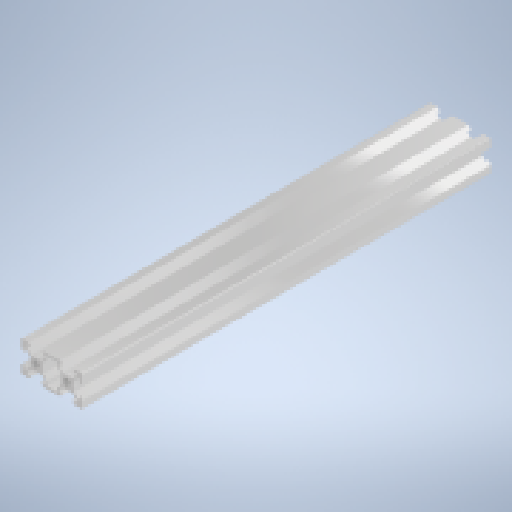
# Autodesk Inventor part: Perfil de alumínio
Saved by Autodesk Inventor 2025.2 (Build 292293000, 293)
## iProperties
Created: 2025-03-01
Part Number: Perfil de alumínio
Material: Alumínio 6061
Document SubType Name: Modeling
Designer: Cliente
Density: 2.7 g/cm^3
Appearance: Alumínio - Escuro
Mass: 397.875 g
Surface Area: 1569.42 cm^2
Volume: 147.361 cm^3
Author: Cliente
Autodesk Inventor part; units mm, degrees
ref_plane "YZ Plane" through (0, 0, 0) normal (1, 0, 0) x (0, 1, 0)
ref_plane "XZ Plane" through (0, 0, 0) normal (0, 1, 0) x (-1, 0, 0)
ref_plane "XY Plane" through (0, 0, 0) normal (0, 0, 1) x (1, 0, 0)
sketch "Esboço1" plane through (0, 0, 0) normal (0, 0, 1) x (1, 0, 0)
  line L0 (20, -10) -> (-19, -10)
  line L1 (-20, -9) -> (-20, 9)
  line L2 (-19, 10) -> (20, 10)
  line L3 (20, 10) -> (20, -10)
  line L4 (20, -10) -> (-20, 10) construction
  line L5 (-20, -10) -> (20, 10) construction
  arc A0 (-19, 10) -> (-20, 9) centre (-19, 9) ccw
  arc A1 (-20, -9) -> (-19, -10) centre (-19, -9) ccw
  circle A2 centre (-10, 0) radius 2.3
  line L6 (-6, -4) -> (-14, -4)
  line L7 (-14, -4) -> (-14, 4)
  line L8 (-14, 4) -> (-6, 4)
  line L9 (-6, 4) -> (-6, -4)
  line L10 (-6, -4) -> (-14, 4) construction
  line L11 (-14, -4) -> (-6, 4) construction
  line L12 (-13, -10) -> (-7, -10)
  line L13 (-13, -10) -> (-13, -8.2)
  line L14 (-7, -10) -> (-7, -8.2)
  line L15 (-13, -8.2) -> (-14.8, -10)
  line L16 (-13, -8.2) -> (-10.4544, -8.2) construction
  line L17 (-7, -8.2) -> (-5.2, -10)
  line L18 (-7, -8.2) -> (-4.4544, -8.2) construction
  line L19 (-15.5, -8.2) -> (-4.5, -8.2)
  line L20 (-6, -4) -> (0, -10)
  line L21 (-6.9192, -4) -> (-0.4596, -10.4596)
  line L22 (-6, -3.0808) -> (0.4596, -9.5404)
  line L23 (-4.5, -8.2) -> (-4.5, -6.4192)
  arc A3 (-9.5, -4) -> (-10.5, -4) centre (-10, -4) ccw
  arc A4 (-14, -0.5) -> (-14, 0.5) centre (-14, 0) ccw
  line L24 (-18.2, 3) -> (-20, 4.8)
  line L25 (-18.2, 5.5) -> (-18.2, -5.5)
  line L26 (-18.2, -3) -> (-20, -4.8)
  arc A5 (-10.5, 4) -> (-9.5, 4) centre (-10, 4) ccw
  line L27 (-7, 8.2) -> (-5.2, 10)
  line L28 (-4.5, 8.2) -> (-15.5, 8.2)
  line L29 (-13, 8.2) -> (-14.8, 10)
  line L30 (-6.9192, 4) -> (-0.4596, 10.4596)
  line L31 (-6, 3.0808) -> (0.4596, 9.5404)
  line L32 (-14, 3.0808) -> (-20.4596, 9.5404)
  line L33 (-13.0808, 4) -> (-19.5404, 10.4596)
  line L34 (-13.0808, -4) -> (-19.5404, -10.4596)
  line L35 (-14, -3.0808) -> (-20.4596, -9.5404)
  line L36 (-15.5, -8.2) -> (-15.5, -6.4192)
  line L37 (-18.2, -5.5) -> (-16.4192, -5.5)
  line L38 (-18.2, 5.5) -> (-16.4192, 5.5)
  line L39 (-15.5, 8.2) -> (-15.5, 6.4192)
  line L40 (-4.5, 8.2) -> (-4.5, 6.4192)
  line L41 (0, 0) -> (0, 4)
  arc A6 (20, 9) -> (19, 10) centre (19, 9) ccw
  arc A7 (19, -10) -> (20, -9) centre (19, -9) ccw
  circle A8 centre (10, 0) radius 2.3
  line L42 (6, -4) -> (14, -4)
  line L43 (14, -4) -> (14, 4)
  line L44 (14, 4) -> (6, 4)
  line L45 (6, 4) -> (6, -4)
  line L46 (13, -8.2) -> (14.8, -10)
  line L47 (7, -8.2) -> (5.2, -10)
  line L48 (15.5, -8.2) -> (4.5, -8.2)
  line L49 (6.9192, -4) -> (0.4596, -10.4596)
  line L50 (6, -3.0808) -> (-0.4596, -9.5404)
  line L51 (4.5, -8.2) -> (4.5, -6.4192)
  arc A9 (10.5, -4) -> (9.5, -4) centre (10, -4) ccw
  arc A10 (14, 0.5) -> (14, -0.5) centre (14, 0) ccw
  line L52 (18.2, 3) -> (20, 4.8)
  line L53 (18.2, 5.5) -> (18.2, -5.5)
  line L54 (18.2, -3) -> (20, -4.8)
  arc A11 (9.5, 4) -> (10.5, 4) centre (10, 4) ccw
  line L55 (7, 8.2) -> (5.2, 10)
  line L56 (4.5, 8.2) -> (15.5, 8.2)
  line L57 (13, 8.2) -> (14.8, 10)
  line L58 (6.9192, 4) -> (0.4596, 10.4596)
  line L59 (6, 3.0808) -> (-0.4596, 9.5404)
  line L60 (14, 3.0808) -> (20.4596, 9.5404)
  line L61 (13.0808, 4) -> (19.5404, 10.4596)
  line L62 (13.0808, -4) -> (19.5404, -10.4596)
  line L63 (14, -3.0808) -> (20.4596, -9.5404)
  line L64 (15.5, -8.2) -> (15.5, -6.4192)
  line L65 (18.2, -5.5) -> (16.4192, -5.5)
  line L66 (18.2, 5.5) -> (16.4192, 5.5)
  line L67 (15.5, 8.2) -> (15.5, 6.4192)
  line L68 (4.5, 8.2) -> (4.5, 6.4192)
  line L69 (-3.2, -5.8808) -> (-3.2, -10)
  line L70 (-3.2, 5.8808) -> (-3.2, 10)
  line L71 (3.2, -5.8808) -> (3.2, -10)
  line L72 (3.2, 5.8808) -> (3.2, 10)
  line L73 (-4.5, 8.2) -> (4.5, 8.2)
  line L74 (-4.5, -8.2) -> (4.5, -8.2)
  line L75 (-10, 4) -> (-10, 3.5)
  line L76 (-10, -4) -> (-10, -3.5)
  line L77 (-14, 0) -> (-13.5, 0)
  line L78 (10, 4) -> (10, 3.5)
  line L79 (14, 0) -> (13.5, 0)
  line L80 (10, -4) -> (10, -3.5)
  line L81 (0, 0) -> (-2, 0)
  arc A12 (-9.5, -4) -> (-10.5, -4) centre (-10, -4.375) ccw
  arc A13 (-14, -0.5) -> (-14, 0.5) centre (-14.375, 0) ccw
  arc A14 (-10.5, 4) -> (-9.5, 4) centre (-10, 4.375) ccw
  arc A15 (10.5, -4) -> (9.5, -4) centre (10, -4.375) ccw
  arc A16 (14, 0.5) -> (14, -0.5) centre (14.375, 0) ccw
  arc A17 (9.5, 4) -> (10.5, 4) centre (10, 4.375) ccw
  point P0 (-20, 0)
  point P1 (-10, -10)
  point P2 (-10, -8.2)
  point P3 (-18.2, 0)
  point P4 (-10, 8.2)
  point P5 (-3.5808, 5.5)
  point P6 (19.0777, 9.997)
  point P7 (-3.2, 8.2)
  point P8 (3.2, 8.2)
  point P9 (3.2, -8.2)
  point P10 (-3.2, -8.2)
  dimension "d0" = 40
  dimension "d1" = 20
  dimension "d2" = 1
  dimension "d3" = 4.6
  dimension "d4" = 10
  dimension "d5" = 8
  dimension "d6" = 8
  dimension "d7" = 6
  dimension "d8" = 1.8
  dimension "d9" = 1.8
  dimension "d10" = 135
  dimension "d11" = 45
  dimension "d12" = 11
  dimension "d13" = 0.65
  dimension "d14" = 0.65
  dimension "d16" = 0.5
  dimension "d19" = 180
  dimension "d23" = 360
  dimension "d25" = 1.3
  dimension "d29" = 0.625
  dimension "d32" = 180
  constraints: 164 end point, 67 symmetric about line, 43 point on line, 39 point on circle, 18 centre point, 8 midpoint, 8 parallel, 7 horizontal, 7 perpendicular, 5 vertical, 4 tangent, 3 horizontal alignment, 3 vertical alignment, 2 equal length, 1 collinear, 1 equal radius, 76 other
  measures "d0" distance of L4.end L2.end
  measures "d1" distance of L5.start L4.end
  measures "d2" radius of A0
  measures "d3" diameter of A2
  measures "d4" distance of point (-20, 0) A2.centre
  measures "d5" distance of L7.end L8.end
  measures "d6" distance of L6.end L7.end
  measures "d7" distance of L12.start L12.end
  measures "d8" distance of L12.start L13.end
  measures "d9" distance of L12.end L14.end
  measures "d10" angle of L15 L16
  measures "d11" angle of L17 L18
  measures "d12" distance of L19.start L19.end
  measures "d13" distance between parallel lines of L20 L21
  measures "d14" distance between parallel lines of L20 L22
  measures "d16" radius of A3
  measures "d25" distance between parallel lines of L23 L69
  measures "d29" radius of A12
extrude "Extrusão1" add sketch "Esboço1" against normal blind 262.8 contours L0 L46 L48 L64 L62 | L62 L42 L43 L63 A7 | L0 L71 L74 L48 L47 | L63 L65 L53 L54 L3 | L0 L49 L74 L71 | L42 A9 L45 L44 A11 L43 A10 | L0 L20 L50 L74 L49 | L71 L49 L51 L74 | A15 L80 A9 | L0 L21 L74 L20 | L71 L50 L45 L42 L49 | L52 L53 L66 L60 L3 | A10 L79 A16 | L80 A15 A9 | L0 L69 L74 L21 | L20 L74 L22 L50 | L50 L22 L74 | A10 A16 L79 | L0 L17 L19 L74 L69 | L60 L43 L44 L61 A6 | L74 L23 L21 L69 | L21 L6 L20 L69 | L20 L9 L22 L69 | L59 L72 L58 L44 L45 | L61 L67 L56 L57 L2 | L6 A3 L7 A4 L8 A5 L9 | L15 L0 A1 L34 L36 L19 | L9 L8 L30 L70 L31 | L73 L31 L59 | L59 L31 L73 L30 L2 L58 | L72 L73 L68 L58 | A12 L76 A3 | A17 L78 A11 | L58 L2 L72 L73 | L72 L2 L55 L56 L73 | A11 L78 A17 | L34 A1 L35 L7 L6 | L76 A12 A3 | L30 L40 L73 L70 | L73 L70 L2 L30 | A5 L75 A14 | L73 L28 L27 L2 L70 | A1 L1 L26 L25 L37 L35 | A5 A14 L75 | A13 L77 A4 | L8 L7 L32 A0 L33 | L28 L39 L33 A0 L2 L29 | L1 A0 L32 L38 L25 L24 | L77 A13 A4
thread "Thread1" size "M5x0.8" class "6H" standard "ANSI Metric M Profile" length 10
thread "Thread2" size "M5x0.8" class "6H" standard "ANSI Metric M Profile" length 10
thread "Thread3" size "M5x0.8" class "6H" standard "ANSI Metric M Profile" length 10
thread "Thread4" size "M5x0.8" class "6H" standard "ANSI Metric M Profile" length 10
